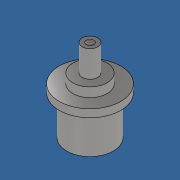
# Autodesk Inventor part: Esempio-003
Saved by Autodesk Inventor 2021.1 (Build 251245000, 245)
## iProperties
Created: 2024-05-31
Part Number: Esempio-003
Material: Acciaio inossidabile
Document SubType Name: Modeling
Designer: UT
Mass: 209.996 g
Surface Area: 69.9499 cm^2
Volume: 26.2495 cm^3
Density: 8 g/cm^3
Appearance: Semilucidato
Author: UT
Autodesk Inventor part; units mm, degrees
ref_plane "YZ Plane" through (0, 0, 0) normal (1, 0, 0) x (0, 1, 0)
ref_plane "XZ Plane" through (0, 0, 0) normal (0, 1, 0) x (-1, 0, 0)
ref_plane "XY Plane" through (0, 0, 0) normal (0, 0, 1) x (1, 0, 0)
sketch "Schizzo1" plane through (0, 0, 0) normal (0, 0, 1) x (1, 0, 0)
  line L0 (0, 63.6) -> (0, -10.6) projected
  line L1 (-5, 53) -> (-5, 36)
  line L2 (-11, 30) -> (-19.75, 30)
  line L3 (-19.75, 30) -> (-19.75, 25)
  line L4 (-19.75, 25) -> (-15, 25)
  line L5 (-15, 25) -> (-15, 0)
  line L6 (-15, 0) -> (0, 0)
  line L7 (0, 0) -> (0, 53)
  line L8 (-5, 53) -> (0, 53)
  line L9 (-11, 30) -> (-11, 36)
  line L10 (-11, 36) -> (-5, 36)
  dimension "d0" = 30
  dimension "d1" = 5
  dimension "d2" = 22
  dimension "d3" = 6
  dimension "d4" = 17
  dimension "d5" = 10
  dimension "d6" = 25
  dimension "d7" = 39.5
  constraints: 20 end point, 7 perpendicular, 2 vertical, 1 point on line
  measures "d0" diameter of L5 L0
  measures "d1" distance of L2.end L3.end
  measures "d2" diameter of L9 L0
  measures "d3" distance of L2.start L9.end
  measures "d4" distance of L1.start L1.end
  measures "d5" diameter of L1 L0
  measures "d6" distance of L4.end L5.end
  measures "d7" diameter of L3 L0
revolve "Rivoluzione1" add sketch "Schizzo1" angle 360 about axis through (0, 0, 0) along (0, -1, 0)
sketch "Schizzo2" plane through (0, 0, 0) normal (0, -1, 0) x (1, 0, 0)
  circle A0 centre (0, 0) radius 15 projected
hole "Foro1" at (0, 0, 0) direction (0, 1, 0) diameter 8.376 depth 16 tip angle 118 thread size "M10x1.5" class "6H" standard "ISO Metric profile"
sketch "Schizzo3" plane through (0, 53, 0) normal (0, 1, 0) x (1, 0, 0)
  circle A0 centre (0, 0) radius 5 projected
hole "Foro2" at (0, 53, 0) direction (0, -1, 0) diameter 4.917 depth 12 tip angle 118 thread size "M6x1" class "6H" standard "ISO Metric profile"
